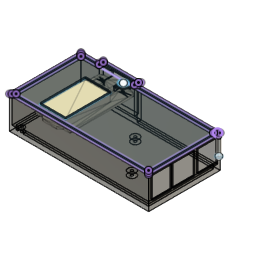
heltec weather node pcb v1.2 (Autodesk Fusion 360 design; units mm, degrees)
Autodesk Fusion 360 part; units mm, degrees
sketch "Skizze2" plane through (0, 0, 0) normal (0, 0, 1) x (1, 0, 0)
  line L0 (0, 0) -> (98, 0)
  line L1 (98, 0) -> (98, 48)
  line L2 (98, 48) -> (0, 48)
  line L3 (0, 48) -> (0, 0)
  line L4 (99.5, -1.5) -> (99.5, 49.5)
  line L5 (-1.5, 49.5) -> (-1.5, -1.5)
  line L6 (-1.5, -1.5) -> (99.5, -1.5)
  line L7 (-2.5, -2.5) -> (100.5, -2.5)
  line L8 (100.5, -2.5) -> (100.5, 50.5)
  line L9 (-2.5, 50.5) -> (-2.5, -2.5)
  line L10 (38, 49.5) -> (38, 52.5)
  line L11 (38, 52.5) -> (12, 52.5)
  line L12 (12, 52.5) -> (12, 49.5)
  line L13 (100.5, 50.5) -> (39, 50.5)
  line L14 (11, 50.5) -> (-2.5, 50.5)
  line L15 (99.5, 49.5) -> (38, 49.5)
  line L16 (12, 49.5) -> (-1.5, 49.5)
  line L17 (11, 50.5) -> (-2.5, 50.5)
  line L18 (-2.5, 50.5) -> (-2.5, -2.5)
  line L19 (-2.5, -2.5) -> (100.5, -2.5)
  line L20 (100.5, -2.5) -> (100.5, 50.5)
  line L21 (100.5, 50.5) -> (39, 50.5)
  line L22 (39, 50.5) -> (39, 53.5)
  line L23 (39, 53.5) -> (11, 53.5)
  line L24 (11, 53.5) -> (11, 50.5)
  dimension "d8" = 98
  dimension "d9" = 48
  dimension "d24" = 26
  dimension "d25" = 3
  dimension "d26" = 13.5
  dimension "d27" = 1
  constraint horizontal L0
  constraint vertical L1
  constraint horizontal L2
  constraint vertical L3
  constraint coincident L0.start L3.end
  constraint vertical L10
  constraint horizontal L11
  constraint vertical L12
  constraint collinear L13 L14
  constraint collinear L15 L16
  measures "d8" distance of L0.start L0.end
  measures "d9" distance of L0.end L1.end
  measures "d24" distance of L12.end L10.start
  measures "d25" distance of L12.end L11.end
  measures "d26" distance of L5 L12
extrude "Extrusion1" add sketch "Skizze2" against normal blind 1 contours L0 L1 L2 L3 | L4 L5 L6 L10 L11 L12 L15 L16 | L7 L8 L9 L13 L14 L17 L18 L19 L20 L21 L22 L23 L24 makes body 1
extrude "Extrusion2" add sketch "Skizze2" along normal blind 3 separate body contours L4 L5 L6 L10 L11 L12 L15 L16 makes body 2
extrude "Extrusion3" add sketch "Skizze2" along normal blind 4.6 contours L7 L8 L9 L13 L14 L17 L18 L19 L20 L21 L22 L23 L24 bodies 1 2
other "Grundnetzelement1"
other "Ändern2"
extrude "Extrusion4" add 1 faces at (65.8333, -2.1667, 4.6) along direction (0, 0, 1) blind 18.4 on bodies 1 bodies 1
other "Ändern1"
sketch "Skizze3" plane through (100.5, 0, 0) normal (1, 0, 0) x (0, 1, 0)
  line L0 (-2.5, 23) -> (-2.5, -1)
  line L1 (-2.5, -1) -> (50.5, -1)
  line L2 (50.5, -1) -> (50.5, 23)
  line L3 (50.5, 23) -> (-2.5, 23)
  line L4 (0.1, 4.9717) -> (14.35, 4.9717)
  line L5 (14.35, 4.9717) -> (14.35, 20.9717)
  line L6 (14.35, 20.9717) -> (0.1, 20.9717)
  line L7 (0.1, 20.9717) -> (0.1, 4.9717)
  line L8 (34, 5) -> (48.25, 5)
  line L9 (48.25, 5) -> (48.25, 21)
  line L10 (48.25, 21) -> (34, 21)
  line L11 (34, 21) -> (34, 5)
  line L12 (15.5, 5) -> (31.5, 5)
  line L13 (31.5, 5) -> (31.5, 21)
  line L14 (31.5, 21) -> (15.5, 21)
  line L15 (15.5, 21) -> (15.5, 5)
  dimension "d17" = 14.25
  dimension "d18" = 16
  dimension "d19" = 14.25
  dimension "d20" = 16
  dimension "d22" = 16
  dimension "d23" = 16
  dimension "d64" = 2.5
  dimension "d65" = 1.15
  dimension "d66" = 6
  dimension "d67" = 2.6
  constraint horizontal L4
  constraint vertical L5
  constraint horizontal L6
  constraint vertical L7
  constraint horizontal L8
  constraint vertical L9
  constraint horizontal L10
  constraint vertical L11
  constraint horizontal L12
  constraint vertical L13
  constraint horizontal L14
  constraint vertical L15
  measures "d17" distance of L8.start L8.end
  measures "d18" distance of L8.start L10.end
  measures "d19" distance of L4.start L4.end
  measures "d20" distance of L12.start L12.end
  measures "d22" distance of L4.end L5.end
  measures "d23" distance of L12.end L13.end
  measures "d64" distance of L11 L13
  measures "d65" distance of L5 L15
  measures "d66" distance of L1 L8
  measures "d67" distance of L0 L7
extrude "Extrusion5" cut sketch "Skizze3" against normal blind 1 contours L4 L5 L6 L7 | L8 L9 L10 L11 | L12 L13 L14 L15 bodies 1
sketch "Skizze4" plane through (0, 53.5, 0) normal (0, 1, 0) x (-1, 0, 0)
  line L0 (-39, 23) -> (-39, -1)
  line L1 (-39, -1) -> (-11, -1)
  line L2 (-11, -1) -> (-11, 23)
  line L3 (-11, 23) -> (-39, 23)
  line L4 (-31.3766, 22.0551) -> (-18.3766, 22.0551)
  line L5 (-18.3766, 22.0551) -> (-18.3766, 15.0551)
  line L6 (-18.3766, 15.0551) -> (-31.3766, 15.0551)
  line L7 (-31.3766, 15.0551) -> (-31.3766, 22.0551)
  dimension "d30" = 13
  dimension "d31" = 7
  constraint horizontal L4
  constraint vertical L5
  constraint horizontal L6
  constraint vertical L7
  measures "d30" distance of L5 L7
  measures "d31" distance of L4 L6
extrude "Extrusion6" cut sketch "Skizze4" against normal blind 1 contours L4 L5 L6 L7 bodies 1
sketch "Skizze5" plane through (0, 0, 23) normal (0, 0, 1) x (-1, 0, 0)
  line L0 (-12, -49.5) -> (-12, -52.5)
  line L1 (-12, -52.5) -> (-38, -52.5)
  line L2 (-38, -52.5) -> (-38, -49.5)
  line L3 (-38, -49.5) -> (-99.5, -49.5)
  line L4 (-99.5, -49.5) -> (-99.5, 1.5)
  line L5 (-99.5, 1.5) -> (1.5, 1.5)
  line L6 (1.5, 1.5) -> (1.5, -49.5)
  line L7 (1.5, -49.5) -> (-12, -49.5)
  line L8 (-11, -53.5) -> (-11, -50.5)
  line L9 (-11, -50.5) -> (2.5, -50.5)
  line L10 (2.5, -50.5) -> (2.5, 2.5)
  line L11 (2.5, 2.5) -> (-100.5, 2.5)
  line L12 (-100.5, 2.5) -> (-100.5, -50.5)
  line L13 (-100.5, -50.5) -> (-39, -50.5)
  line L14 (-39, -50.5) -> (-39, -53.5)
  line L15 (-39, -53.5) -> (-11, -53.5)
  line L16 (0, 0) -> (0, -48)
  line L17 (0, -48) -> (-98, -48)
  line L18 (-98, -48) -> (-98, 0)
  line L19 (-98, 0) -> (0, 0)
  line L20 (-12, -49.5) -> (1.5, -49.5)
  line L21 (1.5, -49.5) -> (1.5, 1.5)
  line L22 (1.5, 1.5) -> (-99.5, 1.5)
  line L23 (-99.5, 1.5) -> (-99.5, -49.5)
  line L24 (-38, -49.5) -> (-38, -52.5)
  line L25 (-38, -52.5) -> (-12, -52.5)
  line L26 (-12, -52.5) -> (-12, -49.5)
  line L27 (0, 0) -> (-98, 0)
  line L28 (-98, 0) -> (-98, -48)
  line L29 (-98, -48) -> (0, -48)
  line L30 (0, -48) -> (0, 0)
  line L31 (-34.323, -2.2517) -> (-15.6501, -2.2517)
  line L32 (-15.6501, -2.2517) -> (-15.6501, -35.5925)
  line L33 (-15.6501, -35.5925) -> (-34.323, -35.5925)
  line L34 (-34.323, -35.5925) -> (-34.323, -2.2517)
  line L35 (-99.4, 1.4) -> (1.4, 1.4)
  line L36 (1.4, 1.4) -> (1.4, -49.4)
  line L37 (1.4, -49.4) -> (-12.1, -49.4)
  line L38 (-12.1, -49.4) -> (-12.1, -52.4)
  line L39 (-12.1, -52.4) -> (-37.9, -52.4)
  line L40 (-37.9, -52.4) -> (-37.9, -49.4)
  line L41 (-37.9, -49.4) -> (-99.4, -49.4)
  line L42 (-99.4, -49.4) -> (-99.4, 1.4)
  line L43 (-98.6, 0.6) -> (0.6, 0.6)
  line L44 (0.6, 0.6) -> (0.6, -48.6)
  line L45 (0.6, -48.6) -> (-12.9, -48.6)
  line L46 (-12.9, -48.6) -> (-12.9, -51.6)
  line L47 (-12.9, -51.6) -> (-37.1, -51.6)
  line L48 (-37.1, -51.6) -> (-37.1, -48.6)
  line L49 (-37.1, -48.6) -> (-98.6, -48.6)
  line L50 (-98.6, -48.6) -> (-98.6, 0.6)
  circle A0 centre (-32.7405, -46.6) radius 1.75
  circle A1 centre (-32.7405, -46.6) radius 2.95
  circle A2 centre (-115, -35) radius 2
  circle A3 centre (-115, -35) radius 1.375
  line L51 (-99.5, -49.5) -> (-38, -49.5)
  line L52 (-31.3557, -52.4) -> (-31.3557, -51.6)
  line L53 (-18.3643, -52.4) -> (-18.3643, -51.6)
  dimension "d34" = 0.1
  dimension "d35" = 0.8
  dimension "d38" = 3.5
  dimension "d39" = 5.9
  dimension "d42" = 4
  dimension "d43" = 2.75
  dimension "d62" = 5
  dimension "d63" = 16.0075
  constraint horizontal L31
  constraint vertical L32
  constraint horizontal L33
  constraint vertical L34
  constraint concentric A0 A1
  constraint concentric A2 A3
  constraint coincident L39 L52.start
  constraint coincident L47 L52.end
  constraint perpendicular L47 L52
  constraint coincident L39 L53.start
  constraint coincident L47 L53.end
  constraint perpendicular L47 L53
  measures "d38" diameter of A0
  measures "d39" diameter of A1
  measures "d42" diameter of A2
  measures "d43" diameter of A3
  measures "d62" distance of L47 A0.centre
  measures "d63" distance of L33 L47
extrude "Extrusion7" add sketch "Skizze5" along normal blind 1 separate body contours L0 L1 L2 L3 L4 L5 L6 L7 L20 L21 L22 L23 L24 L25 L26 L51 | L8 L9 L10 L11 L12 L13 L14 L15 | L16 L17 L18 L19 L27 L28 L29 L30 A1 | L17 L29 A0 A1 | L17 L29 A0 A1 | L35 L36 L37 L38 L39 L40 L41 L42 L43 L44 L45 L46 L47 L48 L49 L50 L52 L53 | L39 L47 L52 L53 | L43 L44 L45 L46 L47 L48 L49 L50 makes body 3
extrude "Extrusion8" add sketch "Skizze5" against normal blind 2 separate body contours L35 L36 L37 L38 L39 L40 L41 L42 L43 L44 L45 L46 L47 L48 L49 L50 L52 L53 makes body 4
extrude "Extrusion16" add sketch "Skizze5" against normal blind 1 separate body contours L39 L47 L52 L53 makes body 5
combine "Kombinieren1" operation add target body 3 tool bodies 4 5
extrude "Extrusion9" add sketch "Skizze5" against normal blind 2 contours L17 L29 A0 A1 | L17 L29 A0 A1 bodies 3
extrude "Extrusion10" add sketch "Skizze5" along normal blind 12 separate body contours A3 makes body 6
extrude "Extrusion11" add sketch "Skizze5" along normal blind 0.4 contours A2 bodies 6
sketch "Skizze6" plane through (0, 0, 0) normal (0, 0, 1) x (-1, 0, 0)
  line L0 (0, 0) -> (-98, 0)
  line L1 (-98, 0) -> (-98, -48)
  line L2 (-98, -48) -> (0, -48)
  line L3 (0, -48) -> (0, 0)
  circle A0 centre (-51.57, -36.5648) radius 3
  circle A1 centre (-71.9558, -13.7155) radius 3
  circle A2 centre (-3.3803, -0.9481) radius 2
  circle A3 centre (-51.57, -36.5648) radius 0.925
  circle A4 centre (-71.9558, -13.7155) radius 0.925
  circle A5 centre (-3.3803, -0.9481) radius 0.925
  dimension "d54" = 6
  dimension "d55" = 6
  dimension "d56" = 4
  dimension "d57" = 1.85
  dimension "d58" = 1.85
  dimension "d59" = 1.85
  constraint concentric A0 A3
  constraint concentric A1 A4
  constraint concentric A2 A5
  measures "d54" diameter of A1
  measures "d55" diameter of A0
  measures "d56" diameter of A2
  measures "d57" diameter of A3
  measures "d58" diameter of A4
  measures "d59" diameter of A5
extrude "Extrusion15" add sketch "Skizze6" along normal blind 3 contours L0 A2 | A0 | A1 picked at (-4.735, -1.8691) bodies 1
equation "d13 = 8.5 mm + 2.5 mm + 5 mm + 2.4 mm"
equation "d39 = 3.5 mm + ( 0.4 * 6 ) * 1 mm"
